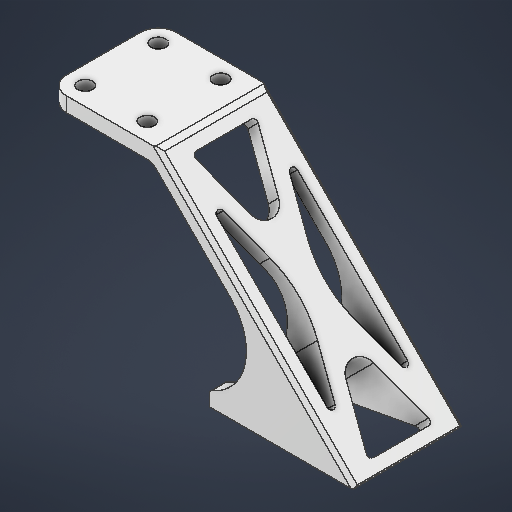
# Autodesk Inventor part: X-axis disc support
Saved by Autodesk Inventor 2026.2 (Build 302298010, 298A)
## iProperties
Created: 2026-04-26
Part Number: X-axis disc support
Material: PBT 플라스틱
Document SubType Name: Modeling
Designer: work
Density: 1.31 g/cm^3
Appearance: 매끄러움 - 흰색
Author: work
Autodesk Inventor part; units mm, degrees
ref_plane "YZ Plane" through (0, 0, 0) normal (1, 0, 0) x (0, 1, 0)
ref_plane "XZ Plane" through (0, 0, 0) normal (0, 1, 0) x (-1, 0, 0)
ref_plane "XY Plane" through (0, 0, 0) normal (0, 0, 1) x (1, 0, 0)
sketch "스케치1" plane through (0, 0, 0) normal (0, 1, 0) x (-1, 0, 0)
  line L0 (0, 10) -> (0, -10) construction
  line L1 (-5, 10) -> (-5, -10)
  line L2 (5, -10) -> (5, 10)
  arc A0 (5, 10) -> (-5, 10) centre (0, 10) ccw
  arc A1 (-5, -10) -> (5, -10) centre (0, -10) ccw
  circle A2 centre (0, 10) radius 2
  circle A3 centre (0, -10) radius 2
  line L3 (0, 15) -> (-25, 15)
  line L4 (-25, 15) -> (-25, -15)
  line L5 (-25, -15) -> (0, -15)
  line L6 (0, -15) -> (0, 15)
  point P0 (0, 0)
  point P1 (0, -15)
  dimension "d0" = 10
  dimension "d1" = 10
  dimension "d2" = 4
  dimension "d3" = 4
  dimension "d4" = 25
  dimension "d5" = 30
  constraints: 16 end point, 5 point on circle, 4 centre point, 4 tangent, 3 parallel, 2 coincident, 1 horizontal, 1 midpoint, 1 perpendicular, 1 vertical
  measures "d0" distance of point (0, 0) L0.end
  measures "d1" diameter of A1
  measures "d2" diameter of A2
  measures "d3" diameter of A3
  measures "d4" distance of L5.end L4.end
  measures "d5" distance of L3.end L4.end
extrude "돌출1" add sketch "스케치1" along normal blind 4 contours A0 L6 A2 A3 A1 L1 | L1 A1 L5 L4 L3 A0 | A0 L2 A1 L6 A3 A2
sketch "스케치2" plane through (0, 0, 15) normal (0, 0, 1) x (1, 0, 0)
  line L0 (25, 0) -> (25, 4) projected
  line L1 (25, 4) -> (79, -50)
  line L2 (79, -50) -> (39, -50)
  line L3 (39, -50) -> (39, -46)
  line L4 (39, -46) -> (69.3431, -46)
  line L5 (69.3431, -46) -> (23.3431, 0)
  line L6 (0, 0) -> (25, 0) projected
  line L7 (25, 0) -> (25, 4) projected
  line L8 (0, 4) -> (25, 4) projected
  line L9 (0, 0) -> (0, 4) projected
  line L10 (0, 0) -> (25, 0) projected
  point P0 (23.3431, 0)
  dimension "d8" = 4
  dimension "d9" = 135
  dimension "d10" = 50
  dimension "d11" = 4
  dimension "d12" = 40
  constraints: 10 end point, 3 perpendicular, 1 parallel, 1 point on line
  measures "d8" distance between parallel lines of L5 L1
  measures "d9" angle of L6 L5
  measures "d10" distance between parallel lines of L6 L2
  measures "d11" distance between parallel lines of L2 L4
  measures "d12" distance from line of L1.end L3
extrude "돌출2" add sketch "스케치2" against normal up to surface (30 mm away) contours L0 L1 L2 L3 L4 L5 L6
fillet "모깎기1" radius 15 1 edges at (69.3431, -46, 0)
fillet "모깎기2" radius 4 1 edges at (23.3431, 0, 0)
chamfer "모따기1" distance 1 angle 45 4 edges at (52, -23, -15) (25, 4, 0) (52, -23, 15) (79, -50, 0)
sketch "스케치3" plane through (25.7071, 3.2929, -14) normal (0.7071068, 0.7071068, 0) x (-0.7071068, 0.7071068, 0)
  line L0 (0, 0) -> (-74.3675, 0) projected
  line L1 (0, 28) -> (0, 0) projected
  line L2 (-74.3675, 28) -> (0, 28) projected
  line L3 (-74.3675, 0) -> (-74.3675, 28) projected
  line L4 (-3, 3) -> (-71.3675, 3)
  line L5 (-71.3675, 3) -> (-71.3675, 25)
  line L6 (-71.3675, 25) -> (-3, 25)
  line L7 (-3, 25) -> (-3, 3)
  line L8 (-3, 25) -> (-71.3675, 3) construction
  line L9 (-71.3675, 25) -> (-3, 3) construction
  line L10 (-64.8384, 3) -> (-3, 22.899)
  line L11 (-3, 5.101) -> (-64.8384, 25)
  line L12 (-9.5291, 25) -> (-71.3675, 5.101)
  line L13 (-9.5291, 3) -> (-71.3675, 22.899)
  arc A0 (-18.8218, 17.8077) -> (-18.8218, 10.1923) centre (-17.5965, 14) ccw
  arc A1 (-55.5458, 10.1923) -> (-55.5458, 17.8077) centre (-56.7711, 14) ccw
  arc A2 (-27.9941, 8.9419) -> (-46.3734, 8.9419) centre (-37.1838, -19.616) ccw
  arc A3 (-46.3734, 19.0581) -> (-27.9941, 19.0581) centre (-37.1838, 47.616) ccw
  point P0 (15.8492, 14)
  dimension "d20" = 3
  dimension "d22" = 4
  dimension "d23" = 2
  dimension "d24" = 2
  dimension "d25" = 2
  dimension "d26" = 4
  dimension "d27" = 4
  dimension "d28" = 30
  dimension "d29" = 30
  constraints: 20 end point, 16 point on line, 8 point on circle, 8 tangent, 4 centre point, 4 parallel, 3 other
  measures "d20" distance between parallel lines of L1 L7
  measures "d22" distance between parallel lines of L11 L13
  measures "d23" distance between parallel lines of L13 L9
  measures "d24" distance between parallel lines of L12 L8
  measures "d25" distance between parallel lines of L8 L10
  measures "d26" radius of A0
  measures "d27" radius of A1
  measures "d28" radius of A3
  measures "d29" radius of A2
extrude "돌출3" cut sketch "스케치3" against normal through all contours L4 L10 A2 L13 | L11 A0 L10 L7 | L5 L13 A1 L12 | L12 A3 L11 L6
fillet "모깎기3" radius 1 11 edges at (67.8322, -46.2774, 11) (67.8322, -46.2774, -11) (26.4142, -0.2426, -8.899) (26.4142, -0.2426, 8.899) (31.031, -4.8594, 11) (31.031, -4.8594, -11) (74.7574, -48.5858, -8.899) (74.7574, -48.5858, 8.899) (39, -46, -13) (39, -46, 0) (39, -46, 13)
sketch "스케치4" plane through (0, 0, 0) normal (0, -1, 0) x (1, 0, 0)
  line L0 (21.6863, 15) -> (21.6863, -15) projected
  line L1 (0, 15) -> (21.6863, 15) projected
  arc A0 (0, 15) -> (-5, 10) centre (0, 10) ccw projected
  line L2 (-5, -10) -> (-5, 10) projected
  arc A1 (-5, -10) -> (0, -15) centre (0, -10) ccw construction
  line L3 (21.6863, -15) -> (0, -15) projected
  circle A2 centre (0, -10) radius 2 construction
  circle A3 centre (0, 10) radius 2 construction
  line L4 (0, 10) -> (17, 10) construction
  line L5 (17, 10) -> (17, -10) construction
  line L6 (17, -10) -> (0, -10) construction
  line L7 (0, -10) -> (0, 10) construction
  circle A4 centre (17, 10) radius 2
  circle A5 centre (17, -10) radius 2
  point P0 (0, 0)
  dimension "d33" = 20
  dimension "d34" = 4
  dimension "d35" = 4
  dimension "d36" = 17
  constraints: 8 end point, 2 centre point, 2 coincident, 2 parallel, 1 horizontal, 1 perpendicular
  measures "d33" distance of L6.end L4.start
  measures "d34" diameter of A4
  measures "d35" diameter of A5
  measures "d36" distance of L4.start L4.end
extrude "돌출4" cut sketch "스케치4" against normal through all
